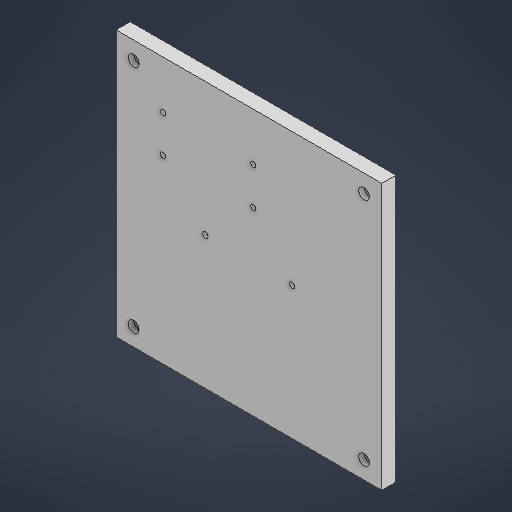
# Autodesk Inventor part: BasePlat
Saved by Autodesk Inventor 2026.2 (Build 302298010, 298A)
## iProperties
Created: 2026-03-09
Part Number: BasePlat
Material: Generic
Document SubType Name: Modeling
Designer: User
Density: 1 g/cm^3
Appearance: Default
Author: User
Autodesk Inventor part; units mm, degrees
ref_plane "YZ Plane" through (0, 0, 0) normal (1, 0, 0) x (0, 1, 0)
ref_plane "XZ Plane" through (0, 0, 0) normal (0, 1, 0) x (-1, 0, 0)
ref_plane "XY Plane" through (0, 0, 0) normal (0, 0, 1) x (1, 0, 0)
sketch "Sketch1" plane through (0, 0, 0) normal (0, 0, 1) x (1, 0, 0)
  line L0 (-69.5106, 38.8723) -> (80.4894, 38.8723)
  line L1 (80.4894, 38.8723) -> (80.4894, -111.1277)
  line L2 (80.4894, -111.1277) -> (-69.5106, -111.1277)
  line L3 (-69.5106, -111.1277) -> (-69.5106, 38.8723)
  point P0 (0, 0)
  dimension "d0" = 150
  dimension "d1" = 150
  constraints: 8 end point, 2 parallel, 1 horizontal, 1 perpendicular
  measures "d0" distance of L0.start L0.end
  measures "d1" distance of L0.end L1.end
extrude "Extrusion1" add sketch "Sketch1" along normal blind 8
sketch "Sketch2" plane through (0, 0, 8) normal (0, 0, 1) x (1, 0, 0)
  line L0 (-110.5528, -36.1277) -> (125.0492, -36.1277)
  line L1 (5.4894, 91.6536) -> (5.4894, -131.8171)
  line L2 (80.4894, 38.8723) -> (-69.5106, 38.8723) projected
  line L3 (-69.5106, -111.1277) -> (80.4894, -111.1277) projected
  line L4 (80.4894, -111.1277) -> (80.4894, 38.8723) projected
  line L5 (-69.5106, 38.8723) -> (-69.5106, -111.1277) projected
  circle A0 centre (-59.4738, 28.8723) radius 3
  point P0 (0, 0)
  dimension "d4" = 75
  dimension "d5" = 75
  dimension "d6" = 75
  dimension "d7" = 75
  dimension "d8" = 235.602
  dimension "d9" = 6
  dimension "d10" = 10
  dimension "d11" = 10.0368
  constraints: 4 end point, 1 centre point, 1 horizontal, 1 vertical
  measures "d4" distance between parallel lines of L0 L2
  measures "d5" distance between parallel lines of L3 L0
  measures "d6" distance between parallel lines of L4 L1
  measures "d7" distance between parallel lines of L5 L1
  measures "d8" distance of L0.start L0.end
  measures "d9" diameter of A0
  measures "d10" distance from line of A0.centre L2
  measures "d11" distance from line of A0.centre L5
extrude "Extrusion2" cut sketch "Sketch2" against normal blind 3 contours A0
sketch "Sketch3" plane through (0, 0, 8) normal (0, 0, 1) x (1, 0, 0)
  circle A0 centre (70.4894, 28.8723) radius 3
  line L0 (80.4894, -111.1277) -> (80.4894, 38.8723) projected
  line L1 (80.4894, 38.8723) -> (-69.5106, 38.8723) projected
  point P0 (0, 0)
  dimension "d14" = 6
  dimension "d15" = 10
  dimension "d16" = 10
  constraints: 1 centre point
  measures "d14" diameter of A0
  measures "d15" distance from line of L0 A0.centre
  measures "d16" distance from line of L1 A0.centre
extrude "Extrusion3" cut sketch "Sketch3" against normal blind 3
sketch "Sketch4" plane through (0, 0, 8) normal (0, 0, 1) x (1, 0, 0)
  circle A0 centre (-59.5106, -101.1277) radius 3
  line L0 (-69.5106, -111.1277) -> (80.4894, -111.1277) projected
  line L1 (-69.5106, 38.8723) -> (-69.5106, -111.1277) projected
  point P0 (0, 0)
  dimension "d19" = 6
  dimension "d20" = 10
  dimension "d21" = 10
  constraints: 1 centre point
  measures "d19" diameter of A0
  measures "d20" distance from line of L0 A0.centre
  measures "d21" distance from line of L1 A0.centre
extrude "Extrusion4" cut sketch "Sketch4" against normal blind 3
sketch "Sketch5" plane through (0, 0, 8) normal (0, 0, 1) x (1, 0, 0)
  circle A0 centre (70.4894, -101.1277) radius 3
  line L0 (80.4894, -111.1277) -> (80.4894, 38.8723) projected
  line L1 (-69.5106, -111.1277) -> (80.4894, -111.1277) projected
  point P0 (0, 0)
  point P1 (80.4894, -36.1277)
  dimension "d24" = 6
  dimension "d25" = 10
  dimension "d26" = 10
  constraints: 1 centre point, 1 midpoint
  measures "d24" diameter of A0
  measures "d25" horizontal distance of point (80.489, -36.128) A0.centre
  measures "d26" distance from line of L1 A0.centre
extrude "Extrusion5" cut sketch "Sketch5" against normal blind 3
sketch "Sketch6" plane through (0, 0, 8) normal (0, 0, 1) x (1, 0, 0)
  line L0 (5.4894, 63.7363) -> (5.4894, -126.7774)
  line L1 (-115.4173, -36.1277) -> (180.3744, -36.1277)
  line L2 (80.4894, -111.1277) -> (80.4894, 38.8723) projected
  line L3 (-69.5106, 38.8723) -> (-69.5106, -111.1277) projected
  line L4 (-69.5106, -111.1277) -> (80.4894, -111.1277) projected
  circle A0 centre (-19.0106, -36.1277) radius 1.5
  point P0 (0, 0)
  dimension "d29" = 75
  dimension "d30" = 75
  dimension "d31" = 75
  dimension "d32" = 3
  dimension "d33" = 24.5
  constraints: 4 end point, 1 centre point, 1 horizontal, 1 point on line, 1 vertical
  measures "d29" distance between parallel lines of L2 L0
  measures "d30" distance between parallel lines of L3 L0
  measures "d31" distance between parallel lines of L4 L1
  measures "d32" diameter of A0
  measures "d33" distance from line of L0 A0.centre
extrude "Extrusion6" cut sketch "Sketch6" against normal through all contours A0 L1 | L1 A0
sketch "Sketch7" plane through (0, 0, 8) normal (0, 0, 1) x (1, 0, 0)
  line L0 (5.4894, 63.4782) -> (5.4894, -142.7531)
  line L1 (-148.0948, -36.1277) -> (151.5698, -36.1277)
  line L2 (80.4894, 38.8723) -> (-69.5106, 38.8723) projected
  line L3 (-69.5106, 38.8723) -> (-69.5106, -111.1277) projected
  circle A0 centre (29.9894, -36.1277) radius 1.5
  point P0 (0, 0)
  dimension "d36" = 75
  dimension "d37" = 75
  dimension "d38" = 3
  dimension "d39" = 24.5
  constraints: 4 end point, 1 centre point, 1 horizontal, 1 point on line, 1 vertical
  measures "d36" distance between parallel lines of L2 L1
  measures "d37" distance between parallel lines of L3 L0
  measures "d38" diameter of A0
  measures "d39" distance from line of A0.centre L0
extrude "Extrusion7" cut sketch "Sketch7" against normal through all contours A0 L1 | L1 A0
sketch "Sketch8" plane through (0, 0, 8) normal (0, 0, 1) x (1, 0, 0)
  line L0 (-42.983, 18.8723) -> (8.017, 18.8723)
  line L1 (8.017, 18.8723) -> (8.017, -9.1277)
  line L2 (8.017, -9.1277) -> (-42.983, -9.1277)
  line L3 (-42.983, -9.1277) -> (-42.983, 18.8723)
  line L4 (-42.983, 18.8723) -> (8.017, -9.1277) construction
  line L5 (8.017, 18.8723) -> (-42.983, -9.1277) construction
  line L6 (-69.5106, 38.8723) -> (-69.5106, -111.1277) projected
  line L7 (80.4894, 38.8723) -> (-69.5106, 38.8723) projected
  point P0 (0, 0)
  point P1 (-17.483, 4.8723)
  dimension "d42" = 51
  dimension "d43" = 28
  dimension "d44" = 26.5277
  dimension "d45" = 20
  constraints: 12 end point, 2 midpoint, 2 parallel, 1 horizontal, 1 perpendicular
  measures "d42" distance of L0.start L0.end
  measures "d43" distance of L0.end L1.end
  measures "d44" distance between parallel lines of L6 L3
  measures "d45" distance between parallel lines of L7 L0
hole "Hole1" at (-42.983, -9.1277, 8) direction (0, 0, -1) diameter 3 end through all
sketch "Sketch9" plane through (0, 0, 8) normal (0, 0, 1) x (1, 0, 0)
  circle A0 centre (-42.983, -9.1277) radius 1.5 projected
  line L0 (-42.983, -9.1277) -> (8.017, -9.1277)
  line L1 (8.017, -9.1277) -> (8.017, 18.8723)
  line L2 (8.017, 18.8723) -> (-44.483, 18.8723)
  line L3 (-44.483, 18.8723) -> (-42.983, -9.1277)
  circle A1 centre (8.017, -9.1277) radius 1.5
  circle A2 centre (8.017, 18.8723) radius 1.5
  arc A3 (-43.733, 18.8723) -> (-42.983, -9.1277) centre (480.0587, 18.8924) ccw
  circle A4 centre (-43.733, 18.8723) radius 1.5
  point P0 (0, 0)
  dimension "d53" = 51
  dimension "d54" = 28
  dimension "d55" = 3
  dimension "d56" = 3
  dimension "d57" = 3
  constraints: 8 end point, 4 centre point, 3 coincident, 2 perpendicular, 2 point on circle, 1 horizontal, 1 point on line, 1 tangent
  measures "d53" distance of L0.start L0.end
  measures "d54" distance of L0.end L1.end
  measures "d55" diameter of A1
  measures "d56" diameter of A2
  measures "d57" diameter of A4
extrude "Extrusion8" cut sketch "Sketch9" against normal through all contours A1 L1 L0 | L0 L1 A1
sketch "Sketch10" plane through (0, 0, 8) normal (0, 0, 1) x (1, 0, 0)
  circle A0 centre (8.017, -9.1277) radius 1.5 projected
  line L0 (8.017, -9.1277) -> (8.017, 11.8723)
  circle A1 centre (8.017, 11.8723) radius 1.5
  point P0 (0, 0)
  dimension "d60" = 21
  dimension "d61" = 3
  constraints: 2 end point, 1 centre point, 1 coincident, 1 vertical
  measures "d60" distance of L0.start L0.end
  measures "d61" diameter of A1
extrude "Extrusion9" cut sketch "Sketch10" against normal through all contours A1
sketch "Sketch11" plane through (0, 0, 8) normal (0, 0, 1) x (1, 0, 0)
  circle A0 centre (8.017, 11.8723) radius 1.5 projected
  line L0 (8.017, 11.8723) -> (-64.3625, 11.8723)
  line L1 (-64.3625, 11.8723) -> (-64.3625, -17.7919)
  line L2 (-64.3625, -17.7919) -> (-42.881, -17.7919)
  line L3 (-42.881, -17.7919) -> (-42.881, 11.8723)
  circle A1 centre (-42.881, 11.8723) radius 1.5
  point P0 (0, 0)
  dimension "d64" = 3
  constraints: 8 end point, 3 perpendicular, 1 centre point, 1 coincident, 1 horizontal, 1 point on line
  measures "d64" diameter of A1
extrude "Extrusion10" cut sketch "Sketch11" against normal through all contours A1 L3 L0 | L0 A1 | L3 A1 L0
body "Solid1"
